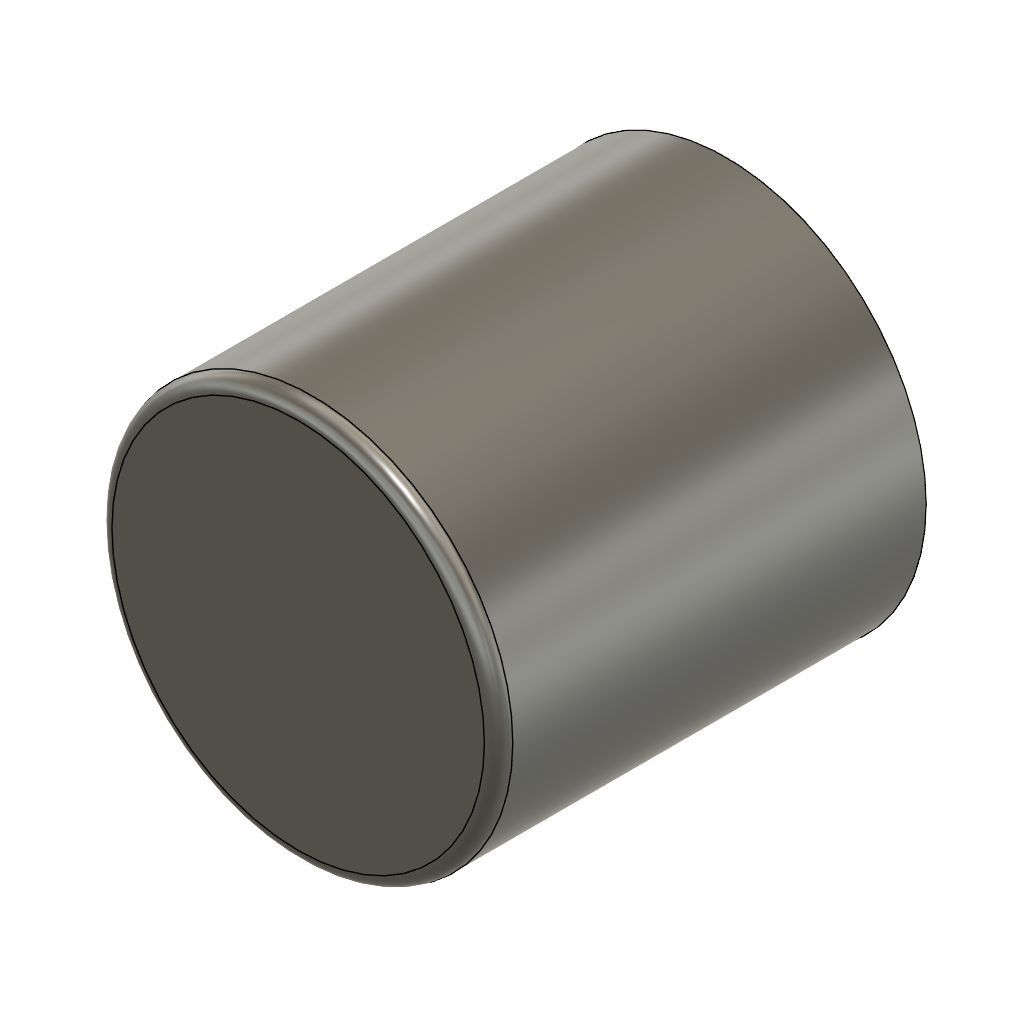
Reconstructed (Autodesk Fusion 360 design; units mm, degrees)
part number: 2026-11-25-22-50-06-317
Autodesk Fusion 360 part; units mm, degrees
sketch "Disc sketch" plane through (0, 0, 0) normal (0, 0, 1) x (1, 0, 0)
  circle A0 centre (0, 0) radius 12.7
extrude "Disc extrude" add sketch "Disc sketch" along normal blind 27.1
fillet "Rim round" radius 0.9 1 edges at (-11.8406, -4.5925, 27.1)
